Fridge Corner (Autodesk Fusion 360 design; units mm, degrees)
Autodesk Fusion 360 part; units mm, degrees
sketch "Sketch1" plane through (0, 0, 0) normal (0, 1, 0) x (1, 0, 0)
  line L0 (22.5, -20) -> (-22.5, -20)
  line L1 (-22.5, -20) -> (-22.5, 20)
  line L2 (-22.5, 20) -> (22.5, 20)
  line L3 (22.5, 20) -> (22.5, -20)
  line L4 (22.5, -20) -> (-22.5, 20) construction
  line L5 (-22.5, -20) -> (22.5, 20) construction
  line L6 (22.5, -20) -> (22.5, 0)
  line L7 (-22.5, 20) -> (-7.5, 20)
  line L8 (-7.5, 20) -> (-7.5, 0)
  line L9 (-7.5, 0) -> (22.5, 0)
  dimension "d1" = 45
  dimension "d2" = 40
  dimension "d5" = 20
  dimension "d6" = 15
  constraint perpendicular L0 L1
  constraint parallel L0 L2
  constraint parallel L1 L3
  constraint horizontal L0
  constraint coincident L4 origin
  constraint coincident L5 origin
  constraint perpendicular L7 L8
  constraint perpendicular L6 L9
  measures "d1" distance of L1.end L2.end
  measures "d2" distance of L0.end L1.end
  measures "d5" distance of L0.start L6.end
  measures "d6" distance of L1.end L7.end
extrude "Extrude1" add sketch "Sketch1" along normal blind 7 contours L0 L1 L2 L3 L6 L7 L8 L9
sketch "Sketch2" plane through (22.5, 0, 0) normal (1, 0, 0) x (0, 0, -1)
  line L0 (-20, 0) -> (0, 0)
  line L1 (0, 0) -> (0, 7)
  line L2 (0, 7) -> (-20, 7)
  line L3 (-20, 7) -> (-20, 0)
  line L4 (-20, 0) -> (-20, 3.5)
  line L5 (-20, 3.5) -> (-12.5, 3.5)
  line L6 (20, 1.95) -> (-45, 1.95)
  line L7 (-45, 1.95) -> (-45, 5.05)
  line L8 (-45, 5.05) -> (20, 5.05)
  line L9 (20, 5.05) -> (20, 1.95)
  line L10 (-12.5, 3.5) -> (-12.5, 1.95)
  line L11 (-12.5, 3.5) -> (-12.5, 5.05)
  point P0 (-12.5, 3.5)
  dimension "d9" = 7.5
  dimension "d10" = 3.1
  constraint coincident L0.start L3.end
  constraint midpoint L3 L4.end
  constraint perpendicular L6 L7
  constraint parallel L6 L8
  constraint parallel L7 L9
  constraint horizontal L6
  constraint coincident P0 L5.end
  constraint midpoint L6 L10.end
  constraint perpendicular L6 L10
  constraint midpoint L8 L11.end
  measures "d9" distance of L4.end P0
  measures "d10" distance of L6.end L7.end
sketch "Sketch3" plane through (0, 0, -20) normal (0, 0, -1) x (-1, 0, 0)
  line L0 (7.5, 0) -> (22.5, 0)
  line L1 (22.5, 0) -> (22.5, 7)
  line L2 (22.5, 7) -> (7.5, 7)
  line L3 (7.5, 7) -> (7.5, 0)
  line L4 (22.5, 0) -> (22.5, 3.5)
  line L5 (22.5, 3.5) -> (14.9, 3.5)
  dimension "d11" = 7.6
  constraint coincident L0.end L1.start
  constraint midpoint L1 L4.end
  measures "d11" distance of L4.end L5.end
extrude "Extrude2" cut sketch "Sketch2" against normal blind 37.4 contours L1 L6 L8 L10 L11 | L1 L6 L8 L9
sketch "Sketch4" plane through (0, 0, 0) normal (0, -1, 0) x (1, 0, 0)
  line L0 (22.5, 0) -> (22.5, 20)
  line L1 (22.5, 20) -> (-22.5, 20)
  line L2 (-22.5, 20) -> (-22.5, -20)
  line L3 (-22.5, -20) -> (-7.5, -20)
  line L4 (-7.5, -20) -> (-7.5, 0)
  line L5 (-7.5, 0) -> (22.5, 0)
  line L6 (-22.5, 20) -> (-22.5, 15)
  line L7 (-22.5, 15) -> (-22.5, 16.6)
  line L8 (-22.5, 15) -> (-12.5, 15)
  line L9 (-22.5, 16.6) -> (-12.5, 16.6)
  line L10 (-12.5, 15) -> (-14.05, 15)
  line L11 (-14.05, 15) -> (-14.05, 20)
  line L12 (-12.5, 15) -> (-12.5, 20)
  dimension "d14" = 5
  dimension "d15" = 1.6
  dimension "d16" = 10
  dimension "d17" = 10
  dimension "d18" = 1.55
  constraint coincident L1.end L2.start
  constraint coincident L1 L11.end
  constraint perpendicular L1 L11
  constraint coincident L1 L12.end
  constraint perpendicular L1 L12
  measures "d14" distance of L1.end L6.end
  measures "d15" distance of L6.end L7.end
  measures "d16" distance of L6.end L8.end
  measures "d17" distance of L7.end L9.end
  measures "d18" distance of L8.end L10.end
extrude "Extrude3" add sketch "Sketch4" along normal blind 5 contours L8 L9 L10 L11 L12 | L2 L6 L7 L8 L9 L11
extrude "Extrude4" add sketch "Sketch4" along normal blind 4 contours L1 L9 L11 L12
fillet "Fillet1" radius 1 5 edges at (-22.5, 3.5, 20) (22.5, 0.975, 0) (22.5, 6.025, 0) (-7.5, 0.975, -20) (-7.5, 6.025, -20)
fillet "Fillet2" radius 3 8 edges at (5, 0, 20) (-22.5, 7, -0.5) (-22.2071, 7, 19.7071) (0.5, 7, 20) (-17.775, 0, 20) (-22.2071, 0, 19.7071) (-22.5, 0, 17.8) (-22.5, 0, -2.5)
